Autodesk Fusion 360 part; units mm, degrees
(part 14 of 28)
  line L615 (34.2647, -13.2503) -> (34.3599, -13.4408)
  line L616 (34.3599, -13.4408) -> (34.3599, -13.6313)
  line L617 (34.3599, -13.6313) -> (34.2647, -13.917)
  line L618 (34.2647, -13.917) -> (33.1218, -15.0598)
  line L619 (33.1218, -15.0598) -> (34.3599, -15.0598)
  line L620 (36.7409, -15.0598) -> (36.7409, -13.0598)
  line L621 (37.598, -15.0598) -> (37.598, -14.0122)
  line L622 (37.598, -14.0122) -> (37.5028, -13.8217)
  line L623 (37.5028, -13.8217) -> (37.3123, -13.7265)
  line L624 (37.3123, -13.7265) -> (37.0266, -13.7265)
  line L625 (37.0266, -13.7265) -> (36.8361, -13.8217)
  line L626 (36.8361, -13.8217) -> (36.7409, -13.917)
  line L627 (38.8361, -15.0598) -> (38.6456, -14.9646)
  line L628 (38.6456, -14.9646) -> (38.5504, -14.8694)
  line L629 (38.5504, -14.8694) -> (38.4552, -14.6789)
  line L630 (38.4552, -14.6789) -> (38.4552, -14.1075)
  line L631 (38.4552, -14.1075) -> (38.5504, -13.917)
  line L632 (38.5504, -13.917) -> (38.6456, -13.8217)
  line L633 (38.6456, -13.8217) -> (38.8361, -13.7265)
  line L634 (38.8361, -13.7265) -> (39.1218, -13.7265)
  line L635 (39.1218, -13.7265) -> (39.3123, -13.8217)
  line L636 (39.3123, -13.8217) -> (39.4075, -13.917)
  line L637 (39.4075, -13.917) -> (39.5028, -14.1075)
  line L638 (39.5028, -14.1075) -> (39.5028, -14.6789)
  line L639 (39.5028, -14.6789) -> (39.4075, -14.8694)
  line L640 (39.4075, -14.8694) -> (39.3123, -14.9646)
  line L641 (39.3123, -14.9646) -> (39.1218, -15.0598)
  line L642 (39.1218, -15.0598) -> (38.8361, -15.0598)
  line L643 (40.6456, -15.0598) -> (40.4552, -14.9646)
  line L644 (40.4552, -14.9646) -> (40.3599, -14.7741)
  line L645 (40.3599, -14.7741) -> (40.3599, -13.0598)
  line L646 (42.1694, -14.9646) -> (41.979, -15.0598)
  line L647 (41.979, -15.0598) -> (41.598, -15.0598)
  line L648 (41.598, -15.0598) -> (41.4075, -14.9646)
  line L649 (41.4075, -14.9646) -> (41.3123, -14.7741)
  line L650 (41.3123, -14.7741) -> (41.3123, -14.0122)
  line L651 (41.3123, -14.0122) -> (41.4075, -13.8217)
  line L652 (41.4075, -13.8217) -> (41.598, -13.7265)
  line L653 (41.598, -13.7265) -> (41.979, -13.7265)
  line L654 (41.979, -13.7265) -> (42.1694, -13.8217)
  line L655 (42.1694, -13.8217) -> (42.2647, -14.0122)
  line L656 (42.2647, -14.0122) -> (42.2647, -14.2027)
  line L657 (42.2647, -14.2027) -> (41.3123, -14.3932)
  line L658 (43.0266, -14.9646) -> (43.2171, -15.0598)
  line L659 (43.2171, -15.0598) -> (43.598, -15.0598)
  line L660 (43.598, -15.0598) -> (43.7885, -14.9646)
  line L661 (43.7885, -14.9646) -> (43.8837, -14.7741)
  line L662 (43.8837, -14.7741) -> (43.8837, -14.6789)
  line L663 (43.8837, -14.6789) -> (43.7885, -14.4884)
  line L664 (43.7885, -14.4884) -> (43.598, -14.3932)
  line L665 (43.598, -14.3932) -> (43.3123, -14.3932)
  line L666 (43.3123, -14.3932) -> (43.1218, -14.2979)
  line L667 (43.1218, -14.2979) -> (43.0266, -14.1075)
  line L668 (43.0266, -14.1075) -> (43.0266, -14.0122)
  line L669 (43.0266, -14.0122) -> (43.1218, -13.8217)
  line L670 (43.1218, -13.8217) -> (43.3123, -13.7265)
  line L671 (43.3123, -13.7265) -> (43.598, -13.7265)
  line L672 (43.598, -13.7265) -> (43.7885, -13.8217)
  line L673 (44.5504, -15.8217) -> (44.6456, -15.7265)
  line L674 (44.6456, -15.7265) -> (44.8361, -15.4408)
  line L675 (44.8361, -15.4408) -> (44.9313, -15.2503)
  line L676 (44.9313, -15.2503) -> (45.0266, -14.9646)
  line L677 (45.0266, -14.9646) -> (45.1218, -14.4884)
  line L678 (45.1218, -14.4884) -> (45.1218, -14.1075)
  line L679 (45.1218, -14.1075) -> (45.0266, -13.6313)
  line L680 (45.0266, -13.6313) -> (44.9313, -13.3456)
  line L681 (44.9313, -13.3456) -> (44.8361, -13.1551)
  line L682 (44.8361, -13.1551) -> (44.6456, -12.8694)
  line L683 (44.6456, -12.8694) -> (44.5504, -12.7741)
  line L684 (-5.555, -16.335) -> (-5.555, -17.235)
  line L685 (-6.005, -16.785) -> (-5.105, -16.785)
  line L686 (-2.1163, -15.6998) -> (-1.9258, -15.6998)
  line L687 (-1.9258, -15.6998) -> (-1.7353, -15.7951)
  line L688 (-1.7353, -15.7951) -> (-1.6401, -15.8903)
  line L689 (-1.6401, -15.8903) -> (-1.5449, -16.0808)
  line L690 (-1.5449, -16.0808) -> (-1.4496, -16.4617)
  line L691 (-1.4496, -16.4617) -> (-1.4496, -16.9379)
  line L692 (-1.4496, -16.9379) -> (-1.5449, -17.3189)
  line L693 (-1.5449, -17.3189) -> (-1.6401, -17.5094)
  line L694 (-1.6401, -17.5094) -> (-1.7353, -17.6046)
  line L695 (-1.7353, -17.6046) -> (-1.9258, -17.6998)
  line L696 (-1.9258, -17.6998) -> (-2.1163, -17.6998)
  line L697 (-2.1163, -17.6998) -> (-2.3068, -17.6046)
  line L698 (-2.3068, -17.6046) -> (-2.402, -17.5094)
  line L699 (-2.402, -17.5094) -> (-2.4972, -17.3189)
  line L700 (-2.4972, -17.3189) -> (-2.5925, -16.9379)
  line L701 (-2.5925, -16.9379) -> (-2.5925, -16.4617)
  line L702 (-2.5925, -16.4617) -> (-2.4972, -16.0808)
  line L703 (-2.4972, -16.0808) -> (-2.402, -15.8903)
  line L704 (-2.402, -15.8903) -> (-2.3068, -15.7951)
  line L705 (-2.3068, -15.7951) -> (-2.1163, -15.6998)
  line L706 (-0.5925, -17.5094) -> (-0.4972, -17.6046)
  line L707 (-0.4972, -17.6046) -> (-0.5925, -17.6998)
  line L708 (-0.5925, -17.6998) -> (-0.6877, -17.6046)
  line L709 (-0.6877, -17.6046) -> (-0.5925, -17.5094)
  line L710 (-0.5925, -17.5094) -> (-0.5925, -17.6998)
  line L711 (0.4551, -17.6998) -> (0.8361, -17.6998)
  line L712 (0.8361, -17.6998) -> (1.0266, -17.6046)
  line L713 (1.0266, -17.6046) -> (1.1218, -17.5094)
  line L714 (1.1218, -17.5094) -> (1.3123, -17.2236)
  line L715 (1.3123, -17.2236) -> (1.4075, -16.8427)
  line L716 (1.4075, -16.8427) -> (1.4075, -16.0808)
  line L717 (1.4075, -16.0808) -> (1.3123, -15.8903)
  line L718 (1.3123, -15.8903) -> (1.2171, -15.7951)
  line L719 (1.2171, -15.7951) -> (1.0266, -15.6998)
  line L720 (1.0266, -15.6998) -> (0.6456, -15.6998)
  line L721 (0.6456, -15.6998) -> (0.4551, -15.7951)
  line L722 (0.4551, -15.7951) -> (0.3599, -15.8903)
  line L723 (0.3599, -15.8903) -> (0.2647, -16.0808)
  line L724 (0.2647, -16.0808) -> (0.2647, -16.557)
  line L725 (0.2647, -16.557) -> (0.3599, -16.7475)
  line L726 (0.3599, -16.7475) -> (0.4551, -16.8427)
  line L727 (0.4551, -16.8427) -> (0.6456, -16.9379)
  line L728 (0.6456, -16.9379) -> (1.0266, -16.9379)
  line L729 (1.0266, -16.9379) -> (1.2171, -16.8427)
  line L730 (1.2171, -16.8427) -> (1.3123, -16.7475)
  line L731 (1.3123, -16.7475) -> (1.4075, -16.557)
  line L732 (2.6456, -15.6998) -> (2.8361, -15.6998)
  line L733 (2.8361, -15.6998) -> (3.0266, -15.7951)
  line L734 (3.0266, -15.7951) -> (3.1218, -15.8903)
  line L735 (3.1218, -15.8903) -> (3.2171, -16.0808)
  line L736 (3.2171, -16.0808) -> (3.3123, -16.4617)
  line L737 (3.3123, -16.4617) -> (3.3123, -16.9379)
  line L738 (3.3123, -16.9379) -> (3.2171, -17.3189)
  line L739 (3.2171, -17.3189) -> (3.1218, -17.5094)
  line L740 (3.1218, -17.5094) -> (3.0266, -17.6046)
  line L741 (3.0266, -17.6046) -> (2.8361, -17.6998)
  line L742 (2.8361, -17.6998) -> (2.6456, -17.6998)
  line L743 (2.6456, -17.6998) -> (2.4551, -17.6046)
  line L744 (2.4551, -17.6046) -> (2.3599, -17.5094)
  line L745 (2.3599, -17.5094) -> (2.2647, -17.3189)
  line L746 (2.2647, -17.3189) -> (2.1694, -16.9379)
  line L747 (2.1694, -16.9379) -> (2.1694, -16.4617)
  line L748 (2.1694, -16.4617) -> (2.2647, -16.0808)
  line L749 (2.2647, -16.0808) -> (2.3599, -15.8903)
  line L750 (2.3599, -15.8903) -> (2.4551, -15.7951)
  line L751 (2.4551, -15.7951) -> (2.6456, -15.6998)
  line L752 (4.5504, -15.6998) -> (4.7409, -15.6998)
  line L753 (4.7409, -15.6998) -> (4.9313, -15.7951)
  line L754 (4.9313, -15.7951) -> (5.0266, -15.8903)
  line L755 (5.0266, -15.8903) -> (5.1218, -16.0808)
  line L756 (5.1218, -16.0808) -> (5.2171, -16.4617)
  line L757 (5.2171, -16.4617) -> (5.2171, -16.9379)
  line L758 (5.2171, -16.9379) -> (5.1218, -17.3189)
  line L759 (5.1218, -17.3189) -> (5.0266, -17.5094)
  line L760 (5.0266, -17.5094) -> (4.9313, -17.6046)
  line L761 (4.9313, -17.6046) -> (4.7409, -17.6998)
  line L762 (4.7409, -17.6998) -> (4.5504, -17.6998)
  line L763 (4.5504, -17.6998) -> (4.3599, -17.6046)
  line L764 (4.3599, -17.6046) -> (4.2647, -17.5094)
  line L765 (4.2647, -17.5094) -> (4.1694, -17.3189)
  line L766 (4.1694, -17.3189) -> (4.0742, -16.9379)
  line L767 (4.0742, -16.9379) -> (4.0742, -16.4617)
  line L768 (4.0742, -16.4617) -> (4.1694, -16.0808)
  line L769 (4.1694, -16.0808) -> (4.2647, -15.8903)
  line L770 (4.2647, -15.8903) -> (4.3599, -15.7951)
  line L771 (4.3599, -15.7951) -> (4.5504, -15.6998)
  line L772 (6.0742, -17.6998) -> (6.0742, -16.3665)
  line L773 (6.0742, -16.557) -> (6.1694, -16.4617)
  line L774 (6.1694, -16.4617) -> (6.3599, -16.3665)
  line L775 (6.3599, -16.3665) -> (6.6456, -16.3665)
  line L776 (6.6456, -16.3665) -> (6.8361, -16.4617)
  line L777 (6.8361, -16.4617) -> (6.9313, -16.6522)
  line L778 (6.9313, -16.6522) -> (6.9313, -17.6998)
  line L779 (6.9313, -16.6522) -> (7.0266, -16.4617)
  line L780 (7.0266, -16.4617) -> (7.2171, -16.3665)
  line L781 (7.2171, -16.3665) -> (7.5028, -16.3665)
  line L782 (7.5028, -16.3665) -> (7.6932, -16.4617)
  line L783 (7.6932, -16.4617) -> (7.7885, -16.6522)
  line L784 (7.7885, -16.6522) -> (7.7885, -17.6998)
  line L785 (8.7409, -17.6998) -> (8.7409, -16.3665)
  line L786 (8.7409, -16.557) -> (8.8361, -16.4617)
  line L787 (8.8361, -16.4617) -> (9.0266, -16.3665)
  line L788 (9.0266, -16.3665) -> (9.3123, -16.3665)
  line L789 (9.3123, -16.3665) -> (9.5028, -16.4617)
  line L790 (9.5028, -16.4617) -> (9.598, -16.6522)
  line L791 (9.598, -16.6522) -> (9.598, -17.6998)
  line L792 (9.598, -16.6522) -> (9.6932, -16.4617)
  line L793 (9.6932, -16.4617) -> (9.8837, -16.3665)
  line L794 (9.8837, -16.3665) -> (10.1694, -16.3665)
  line L795 (10.1694, -16.3665) -> (10.3599, -16.4617)
  line L796 (10.3599, -16.4617) -> (10.4552, -16.6522)
  line L797 (10.4552, -16.6522) -> (10.4552, -17.6998)
  line L798 (14.3599, -15.6046) -> (12.6456, -18.176)
  line L799 (16.9313, -15.6998) -> (17.1218, -15.6998)
  line L800 (17.1218, -15.6998) -> (17.3123, -15.7951)
  line L801 (17.3123, -15.7951) -> (17.4075, -15.8903)
  line L802 (17.4075, -15.8903) -> (17.5028, -16.0808)
  line L803 (17.5028, -16.0808) -> (17.598, -16.4617)
  line L804 (17.598, -16.4617) -> (17.598, -16.9379)
  line L805 (17.598, -16.9379) -> (17.5028, -17.3189)
  line L806 (17.5028, -17.3189) -> (17.4075, -17.5094)
  line L807 (17.4075, -17.5094) -> (17.3123, -17.6046)
  line L808 (17.3123, -17.6046) -> (17.1218, -17.6998)
  line L809 (17.1218, -17.6998) -> (16.9313, -17.6998)
  line L810 (16.9313, -17.6998) -> (16.7409, -17.6046)
  line L811 (16.7409, -17.6046) -> (16.6456, -17.5094)
  line L812 (16.6456, -17.5094) -> (16.5504, -17.3189)
  line L813 (16.5504, -17.3189) -> (16.4552, -16.9379)
  line L814 (16.4552, -16.9379) -> (16.4552, -16.4617)
  line L815 (16.4552, -16.4617) -> (16.5504, -16.0808)
  line L816 (16.5504, -16.0808) -> (16.6456, -15.8903)
  line L817 (16.6456, -15.8903) -> (16.7409, -15.7951)
  line L818 (16.7409, -15.7951) -> (16.9313, -15.6998)
  line L819 (18.4552, -17.5094) -> (18.5504, -17.6046)
  line L820 (18.5504, -17.6046) -> (18.4552, -17.6998)
  line L821 (18.4552, -17.6998) -> (18.3599, -17.6046)
  line L822 (18.3599, -17.6046) -> (18.4552, -17.5094)
  line L823 (18.4552, -17.5094) -> (18.4552, -17.6998)
  line L824 (19.7885, -15.6998) -> (19.979, -15.6998)
  line L825 (19.979, -15.6998) -> (20.1694, -15.7951)
  line L826 (20.1694, -15.7951) -> (20.2647, -15.8903)
  line L827 (20.2647, -15.8903) -> (20.3599, -16.0808)
  line L828 (20.3599, -16.0808) -> (20.4552, -16.4617)
  line L829 (20.4552, -16.4617) -> (20.4552, -16.9379)
  line L830 (20.4552, -16.9379) -> (20.3599, -17.3189)
  line L831 (20.3599, -17.3189) -> (20.2647, -17.5094)
  line L832 (20.2647, -17.5094) -> (20.1694, -17.6046)
  line L833 (20.1694, -17.6046) -> (19.979, -17.6998)
  line L834 (19.979, -17.6998) -> (19.7885, -17.6998)
  line L835 (19.7885, -17.6998) -> (19.598, -17.6046)
  line L836 (19.598, -17.6046) -> (19.5028, -17.5094)
  line L837 (19.5028, -17.5094) -> (19.4075, -17.3189)
  line L838 (19.4075, -17.3189) -> (19.3123, -16.9379)
  line L839 (19.3123, -16.9379) -> (19.3123, -16.4617)
  line L840 (19.3123, -16.4617) -> (19.4075, -16.0808)
  line L841 (19.4075, -16.0808) -> (19.5028, -15.8903)
  line L842 (19.5028, -15.8903) -> (19.598, -15.7951)
  line L843 (19.598, -15.7951) -> (19.7885, -15.6998)
  line L844 (21.1218, -15.6998) -> (22.3599, -15.6998)
  line L845 (22.3599, -15.6998) -> (21.6932, -16.4617)
  line L846 (21.6932, -16.4617) -> (21.979, -16.4617)
  line L847 (21.979, -16.4617) -> (22.1694, -16.557)
  line L848 (22.1694, -16.557) -> (22.2647, -16.6522)
  line L849 (22.2647, -16.6522) -> (22.3599, -16.8427)
  line L850 (22.3599, -16.8427) -> (22.3599, -17.3189)
  line L851 (22.3599, -17.3189) -> (22.2647, -17.5094)
  line L852 (22.2647, -17.5094) -> (22.1694, -17.6046)
  line L853 (22.1694, -17.6046) -> (21.979, -17.6998)
  line L854 (21.979, -17.6998) -> (21.4075, -17.6998)
  line L855 (21.4075, -17.6998) -> (21.2171, -17.6046)
  line L856 (21.2171, -17.6046) -> (21.1218, -17.5094)
  line L857 (24.1694, -15.6998) -> (23.2171, -15.6998)
  line L858 (23.2171, -15.6998) -> (23.1218, -16.6522)
  line L859 (23.1218, -16.6522) -> (23.2171, -16.557)
  line L860 (23.2171, -16.557) -> (23.4075, -16.4617)
  line L861 (23.4075, -16.4617) -> (23.8837, -16.4617)
  line L862 (23.8837, -16.4617) -> (24.0742, -16.557)
  line L863 (24.0742, -16.557) -> (24.1694, -16.6522)
  line L864 (24.1694, -16.6522) -> (24.2647, -16.8427)
  line L865 (24.2647, -16.8427) -> (24.2647, -17.3189)
  line L866 (24.2647, -17.3189) -> (24.1694, -17.5094)
  line L867 (24.1694, -17.5094) -> (24.0742, -17.6046)
  line L868 (24.0742, -17.6046) -> (23.8837, -17.6998)
  line L869 (23.8837, -17.6998) -> (23.4075, -17.6998)
  line L870 (23.4075, -17.6998) -> (23.2171, -17.6046)
  line L871 (23.2171, -17.6046) -> (23.1218, -17.5094)
  line L872 (25.979, -16.3665) -> (25.979, -17.6998)
  line L873 (25.5028, -15.6046) -> (25.0266, -17.0332)
  line L874 (25.0266, -17.0332) -> (26.2647, -17.0332)
  line L875 (26.9313, -15.6998) -> (26.9313, -16.0808)
  line L876 (27.6932, -15.6998) -> (27.6932, -16.0808)
  line L877 (30.6456, -18.4617) -> (30.5504, -18.3665)
  line L878 (30.5504, -18.3665) -> (30.3599, -18.0808)
  line L879 (30.3599, -18.0808) -> (30.2647, -17.8903)
  line L880 (30.2647, -17.8903) -> (30.1694, -17.6046)
  line L881 (30.1694, -17.6046) -> (30.0742, -17.1284)
  line L882 (30.0742, -17.1284) -> (30.0742, -16.7475)
  line L883 (30.0742, -16.7475) -> (30.1694, -16.2713)
  line L884 (30.1694, -16.2713) -> (30.2647, -15.9856)
  line L885 (30.2647, -15.9856) -> (30.3599, -15.7951)
  line L886 (30.3599, -15.7951) -> (30.5504, -15.5094)
  line L887 (30.5504, -15.5094) -> (30.6456, -15.4141)
  line L888 (32.4552, -17.6998) -> (31.3123, -17.6998)
  line L889 (31.8837, -17.6998) -> (31.8837, -15.6998)
  line L890 (31.8837, -15.6998) -> (31.6932, -15.9856)
  line L891 (31.6932, -15.9856) -> (31.5028, -16.176)
  line L892 (31.5028, -16.176) -> (31.3123, -16.2713)
  line L893 (33.2171, -15.8903) -> (33.3123, -15.7951)
  line L894 (33.3123, -15.7951) -> (33.5028, -15.6998)
  line L895 (33.5028, -15.6998) -> (33.979, -15.6998)
  line L896 (33.979, -15.6998) -> (34.1694, -15.7951)
  line L897 (34.1694, -15.7951) -> (34.2647, -15.8903)
  line L898 (34.2647, -15.8903) -> (34.3599, -16.0808)
  line L899 (34.3599, -16.0808) -> (34.3599, -16.2713)
  line L900 (34.3599, -16.2713) -> (34.2647, -16.557)
  line L901 (34.2647, -16.557) -> (33.1218, -17.6998)
  line L902 (33.1218, -17.6998) -> (34.3599, -17.6998)
  line L903 (36.7409, -17.6998) -> (36.7409, -15.6998)
  line L904 (37.598, -17.6998) -> (37.598, -16.6522)
  line L905 (37.598, -16.6522) -> (37.5028, -16.4617)
  line L906 (37.5028, -16.4617) -> (37.3123, -16.3665)
  line L907 (37.3123, -16.3665) -> (37.0266, -16.3665)
  line L908 (37.0266, -16.3665) -> (36.8361, -16.4617)
  line L909 (36.8361, -16.4617) -> (36.7409, -16.557)
  line L910 (38.8361, -17.6998) -> (38.6456, -17.6046)
  line L911 (38.6456, -17.6046) -> (38.5504, -17.5094)
  line L912 (38.5504, -17.5094) -> (38.4552, -17.3189)
  line L913 (38.4552, -17.3189) -> (38.4552, -16.7475)
  line L914 (38.4552, -16.7475) -> (38.5504, -16.557)
  line L915 (38.5504, -16.557) -> (38.6456, -16.4617)
  line L916 (38.6456, -16.4617) -> (38.8361, -16.3665)
  line L917 (38.8361, -16.3665) -> (39.1218, -16.3665)
  line L918 (39.1218, -16.3665) -> (39.3123, -16.4617)
  line L919 (39.3123, -16.4617) -> (39.4075, -16.557)
  line L920 (39.4075, -16.557) -> (39.5028, -16.7475)
  line L921 (39.5028, -16.7475) -> (39.5028, -17.3189)
  line L922 (39.5028, -17.3189) -> (39.4075, -17.5094)
  line L923 (39.4075, -17.5094) -> (39.3123, -17.6046)
  line L924 (39.3123, -17.6046) -> (39.1218, -17.6998)
  line L925 (39.1218, -17.6998) -> (38.8361, -17.6998)
  line L926 (40.6456, -17.6998) -> (40.4552, -17.6046)
  line L927 (40.4552, -17.6046) -> (40.3599, -17.4141)
  line L928 (40.3599, -17.4141) -> (40.3599, -15.6998)
  line L929 (42.1694, -17.6046) -> (41.979, -17.6998)
  line L930 (41.979, -17.6998) -> (41.598, -17.6998)
  line L931 (41.598, -17.6998) -> (41.4075, -17.6046)
  line L932 (41.4075, -17.6046) -> (41.3123, -17.4141)
  line L933 (41.3123, -17.4141) -> (41.3123, -16.6522)
  line L934 (41.3123, -16.6522) -> (41.4075, -16.4617)
  line L935 (41.4075, -16.4617) -> (41.598, -16.3665)
  line L936 (41.598, -16.3665) -> (41.979, -16.3665)
  line L937 (41.979, -16.3665) -> (42.1694, -16.4617)
  line L938 (42.1694, -16.4617) -> (42.2647, -16.6522)
  line L939 (42.2647, -16.6522) -> (42.2647, -16.8427)
  line L940 (42.2647, -16.8427) -> (41.3123, -17.0332)
  line L941 (43.0266, -17.6046) -> (43.2171, -17.6998)
  line L942 (43.2171, -17.6998) -> (43.598, -17.6998)
  line L943 (43.598, -17.6998) -> (43.7885, -17.6046)
  line L944 (43.7885, -17.6046) -> (43.8837, -17.4141)
  line L945 (43.8837, -17.4141) -> (43.8837, -17.3189)
  line L946 (43.8837, -17.3189) -> (43.7885, -17.1284)
  line L947 (43.7885, -17.1284) -> (43.598, -17.0332)
  line L948 (43.598, -17.0332) -> (43.3123, -17.0332)
  line L949 (43.3123, -17.0332) -> (43.1218, -16.9379)
  line L950 (43.1218, -16.9379) -> (43.0266, -16.7475)
  line L951 (43.0266, -16.7475) -> (43.0266, -16.6522)
  line L952 (43.0266, -16.6522) -> (43.1218, -16.4617)
  line L953 (43.1218, -16.4617) -> (43.3123, -16.3665)
  line L954 (43.3123, -16.3665) -> (43.598, -16.3665)
  line L955 (43.598, -16.3665) -> (43.7885, -16.4617)
  line L956 (44.5504, -18.4617) -> (44.6456, -18.3665)
  line L957 (44.6456, -18.3665) -> (44.8361, -18.0808)
  line L958 (44.8361, -18.0808) -> (44.9313, -17.8903)
  line L959 (44.9313, -17.8903) -> (45.0266, -17.6046)
  line L960 (45.0266, -17.6046) -> (45.1218, -17.1284)
  line L961 (45.1218, -17.1284) -> (45.1218, -16.7475)
  line L962 (45.1218, -16.7475) -> (45.0266, -16.2713)
  line L963 (45.0266, -16.2713) -> (44.9313, -15.9856)
  line L964 (44.9313, -15.9856) -> (44.8361, -15.7951)
  line L965 (44.8361, -15.7951) -> (44.6456, -15.5094)
  line L966 (44.6456, -15.5094) -> (44.5504, -15.4141)
  line L967 (-5.2514, -19.7786) -> (-5.2514, -19.0714)
  line L968 (-5.2514, -19.0714) -> (-5.9586, -19.0714)
  line L969 (-5.9586, -19.0714) -> (-5.9586, -19.7786)
  line L970 (-5.9586, -19.7786) -> (-5.2514, -19.7786)
  line L971 (-1.4496, -20.3398) -> (-2.5925, -20.3398)
  line L972 (-2.021, -20.3398) -> (-2.021, -18.3398)
  line L973 (-2.021, -18.3398) -> (-2.2115, -18.6256)
  line L974 (-2.2115, -18.6256) -> (-2.402, -18.816)
  line L975 (-2.402, -18.816) -> (-2.5925, -18.9113)
  line L976 (-0.5925, -20.1494) -> (-0.4972, -20.2446)
  line L977 (-0.4972, -20.2446) -> (-0.5925, -20.3398)
  line L978 (-0.5925, -20.3398) -> (-0.6877, -20.2446)
  line L979 (-0.6877, -20.2446) -> (-0.5925, -20.1494)
  line L980 (-0.5925, -20.1494) -> (-0.5925, -20.3398)
  line L981 (0.7409, -18.3398) -> (0.9313, -18.3398)
  line L982 (0.9313, -18.3398) -> (1.1218, -18.4351)
  line L983 (1.1218, -18.4351) -> (1.2171, -18.5303)
  line L984 (1.2171, -18.5303) -> (1.3123, -18.7208)
  line L985 (1.3123, -18.7208) -> (1.4075, -19.1017)
  line L986 (1.4075, -19.1017) -> (1.4075, -19.5779)
  line L987 (1.4075, -19.5779) -> (1.3123, -19.9589)
  line L988 (1.3123, -19.9589) -> (1.2171, -20.1494)
  line L989 (1.2171, -20.1494) -> (1.1218, -20.2446)
  line L990 (1.1218, -20.2446) -> (0.9313, -20.3398)
  line L991 (0.9313, -20.3398) -> (0.7409, -20.3398)
  line L992 (0.7409, -20.3398) -> (0.5504, -20.2446)
  line L993 (0.5504, -20.2446) -> (0.4551, -20.1494)
  line L994 (0.4551, -20.1494) -> (0.3599, -19.9589)
  line L995 (0.3599, -19.9589) -> (0.2647, -19.5779)
  line L996 (0.2647, -19.5779) -> (0.2647, -19.1017)
  line L997 (0.2647, -19.1017) -> (0.3599, -18.7208)
  line L998 (0.3599, -18.7208) -> (0.4551, -18.5303)
  line L999 (0.4551, -18.5303) -> (0.5504, -18.4351)
  line L1000 (0.5504, -18.4351) -> (0.7409, -18.3398)
  line L1001 (2.6456, -18.3398) -> (2.8361, -18.3398)
  line L1002 (2.8361, -18.3398) -> (3.0266, -18.4351)
  line L1003 (3.0266, -18.4351) -> (3.1218, -18.5303)
  line L1004 (3.1218, -18.5303) -> (3.2171, -18.7208)
  line L1005 (3.2171, -18.7208) -> (3.3123, -19.1017)
  line L1006 (3.3123, -19.1017) -> (3.3123, -19.5779)
  line L1007 (3.3123, -19.5779) -> (3.2171, -19.9589)
  line L1008 (3.2171, -19.9589) -> (3.1218, -20.1494)
  line L1009 (3.1218, -20.1494) -> (3.0266, -20.2446)
  line L1010 (3.0266, -20.2446) -> (2.8361, -20.3398)
  line L1011 (2.8361, -20.3398) -> (2.6456, -20.3398)
  line L1012 (2.6456, -20.3398) -> (2.4551, -20.2446)
  line L1013 (2.4551, -20.2446) -> (2.3599, -20.1494)
  line L1014 (2.3599, -20.1494) -> (2.2647, -19.9589)
  line L1015 (2.2647, -19.9589) -> (2.1694, -19.5779)
  line L1016 (2.1694, -19.5779) -> (2.1694, -19.1017)
  line L1017 (2.1694, -19.1017) -> (2.2647, -18.7208)
  line L1018 (2.2647, -18.7208) -> (2.3599, -18.5303)
  line L1019 (2.3599, -18.5303) -> (2.4551, -18.4351)
  line L1020 (2.4551, -18.4351) -> (2.6456, -18.3398)
  line L1021 (4.5504, -18.3398) -> (4.7409, -18.3398)
  line L1022 (4.7409, -18.3398) -> (4.9313, -18.4351)
  line L1023 (4.9313, -18.4351) -> (5.0266, -18.5303)
  line L1024 (5.0266, -18.5303) -> (5.1218, -18.7208)
  line L1025 (5.1218, -18.7208) -> (5.2171, -19.1017)
  line L1026 (5.2171, -19.1017) -> (5.2171, -19.5779)
  line L1027 (5.2171, -19.5779) -> (5.1218, -19.9589)
  line L1028 (5.1218, -19.9589) -> (5.0266, -20.1494)
  line L1029 (5.0266, -20.1494) -> (4.9313, -20.2446)
  line L1030 (4.9313, -20.2446) -> (4.7409, -20.3398)
  line L1031 (4.7409, -20.3398) -> (4.5504, -20.3398)
  line L1032 (4.5504, -20.3398) -> (4.3599, -20.2446)
  line L1033 (4.3599, -20.2446) -> (4.2647, -20.1494)
  line L1034 (4.2647, -20.1494) -> (4.1694, -19.9589)
  line L1035 (4.1694, -19.9589) -> (4.0742, -19.5779)
  line L1036 (4.0742, -19.5779) -> (4.0742, -19.1017)
  line L1037 (4.0742, -19.1017) -> (4.1694, -18.7208)
  line L1038 (4.1694, -18.7208) -> (4.2647, -18.5303)
  line L1039 (4.2647, -18.5303) -> (4.3599, -18.4351)
  line L1040 (4.3599, -18.4351) -> (4.5504, -18.3398)
  line L1041 (6.0742, -20.3398) -> (6.0742, -19.0065)
  line L1042 (6.0742, -19.197) -> (6.1694, -19.1017)
  line L1043 (6.1694, -19.1017) -> (6.3599, -19.0065)
  line L1044 (6.3599, -19.0065) -> (6.6456, -19.0065)
  line L1045 (6.6456, -19.0065) -> (6.8361, -19.1017)
  line L1046 (6.8361, -19.1017) -> (6.9313, -19.2922)
  line L1047 (6.9313, -19.2922) -> (6.9313, -20.3398)
  line L1048 (6.9313, -19.2922) -> (7.0266, -19.1017)
  line L1049 (7.0266, -19.1017) -> (7.2171, -19.0065)
  line L1050 (7.2171, -19.0065) -> (7.5028, -19.0065)
  line L1051 (7.5028, -19.0065) -> (7.6932, -19.1017)
  line L1052 (7.6932, -19.1017) -> (7.7885, -19.2922)
  line L1053 (7.7885, -19.2922) -> (7.7885, -20.3398)
  line L1054 (8.7409, -20.3398) -> (8.7409, -19.0065)
  line L1055 (8.7409, -19.197) -> (8.8361, -19.1017)
  line L1056 (8.8361, -19.1017) -> (9.0266, -19.0065)
  line L1057 (9.0266, -19.0065) -> (9.3123, -19.0065)
  line L1058 (9.3123, -19.0065) -> (9.5028, -19.1017)
  line L1059 (9.5028, -19.1017) -> (9.598, -19.2922)
  line L1060 (9.598, -19.2922) -> (9.598, -20.3398)
  line L1061 (9.598, -19.2922) -> (9.6932, -19.1017)
  line L1062 (9.6932, -19.1017) -> (9.8837, -19.0065)
  line L1063 (9.8837, -19.0065) -> (10.1694, -19.0065)
  line L1064 (10.1694, -19.0065) -> (10.3599, -19.1017)
  line L1065 (10.3599, -19.1017) -> (10.4552, -19.2922)
  line L1066 (10.4552, -19.2922) -> (10.4552, -20.3398)
  line L1067 (14.3599, -18.2446) -> (12.6456, -20.816)
  line L1068 (16.9313, -18.3398) -> (17.1218, -18.3398)
  line L1069 (17.1218, -18.3398) -> (17.3123, -18.4351)
  line L1070 (17.3123, -18.4351) -> (17.4075, -18.5303)
  line L1071 (17.4075, -18.5303) -> (17.5028, -18.7208)
  line L1072 (17.5028, -18.7208) -> (17.598, -19.1017)
  line L1073 (17.598, -19.1017) -> (17.598, -19.5779)
  line L1074 (17.598, -19.5779) -> (17.5028, -19.9589)
  line L1075 (17.5028, -19.9589) -> (17.4075, -20.1494)
  line L1076 (17.4075, -20.1494) -> (17.3123, -20.2446)
  line L1077 (17.3123, -20.2446) -> (17.1218, -20.3398)
  line L1078 (17.1218, -20.3398) -> (16.9313, -20.3398)
  line L1079 (16.9313, -20.3398) -> (16.7409, -20.2446)
  line L1080 (16.7409, -20.2446) -> (16.6456, -20.1494)
  line L1081 (16.6456, -20.1494) -> (16.5504, -19.9589)
  line L1082 (16.5504, -19.9589) -> (16.4552, -19.5779)
  line L1083 (16.4552, -19.5779) -> (16.4552, -19.1017)
  line L1084 (16.4552, -19.1017) -> (16.5504, -18.7208)
  line L1085 (16.5504, -18.7208) -> (16.6456, -18.5303)
  line L1086 (16.6456, -18.5303) -> (16.7409, -18.4351)
  line L1087 (16.7409, -18.4351) -> (16.9313, -18.3398)
  line L1088 (18.4552, -20.1494) -> (18.5504, -20.2446)
  line L1089 (18.5504, -20.2446) -> (18.4552, -20.3398)
  line L1090 (18.4552, -20.3398) -> (18.3599, -20.2446)
  line L1091 (18.3599, -20.2446) -> (18.4552, -20.1494)
  line L1092 (18.4552, -20.1494) -> (18.4552, -20.3398)
  line L1093 (19.7885, -18.3398) -> (19.979, -18.3398)
  line L1094 (19.979, -18.3398) -> (20.1694, -18.4351)
  line L1095 (20.1694, -18.4351) -> (20.2647, -18.5303)
  line L1096 (20.2647, -18.5303) -> (20.3599, -18.7208)
  line L1097 (20.3599, -18.7208) -> (20.4552, -19.1017)
  line L1098 (20.4552, -19.1017) -> (20.4552, -19.5779)
  line L1099 (20.4552, -19.5779) -> (20.3599, -19.9589)
  line L1100 (20.3599, -19.9589) -> (20.2647, -20.1494)
  line L1101 (20.2647, -20.1494) -> (20.1694, -20.2446)
  line L1102 (20.1694, -20.2446) -> (19.979, -20.3398)
  line L1103 (19.979, -20.3398) -> (19.7885, -20.3398)
  line L1104 (19.7885, -20.3398) -> (19.598, -20.2446)
  line L1105 (19.598, -20.2446) -> (19.5028, -20.1494)
  line L1106 (19.5028, -20.1494) -> (19.4075, -19.9589)
  line L1107 (19.4075, -19.9589) -> (19.3123, -19.5779)
  line L1108 (19.3123, -19.5779) -> (19.3123, -19.1017)
  line L1109 (19.3123, -19.1017) -> (19.4075, -18.7208)
  line L1110 (19.4075, -18.7208) -> (19.5028, -18.5303)
  line L1111 (19.5028, -18.5303) -> (19.598, -18.4351)
  line L1112 (19.598, -18.4351) -> (19.7885, -18.3398)
  line L1113 (21.1218, -18.3398) -> (22.3599, -18.3398)
  line L1114 (22.3599, -18.3398) -> (21.6932, -19.1017)
  line L1115 (21.6932, -19.1017) -> (21.979, -19.1017)
  line L1116 (21.979, -19.1017) -> (22.1694, -19.197)
  line L1117 (22.1694, -19.197) -> (22.2647, -19.2922)
  line L1118 (22.2647, -19.2922) -> (22.3599, -19.4827)
  line L1119 (22.3599, -19.4827) -> (22.3599, -19.9589)
  line L1120 (22.3599, -19.9589) -> (22.2647, -20.1494)
  line L1121 (22.2647, -20.1494) -> (22.1694, -20.2446)
  line L1122 (22.1694, -20.2446) -> (21.979, -20.3398)
  line L1123 (21.979, -20.3398) -> (21.4075, -20.3398)
  line L1124 (21.4075, -20.3398) -> (21.2171, -20.2446)
  line L1125 (21.2171, -20.2446) -> (21.1218, -20.1494)
  line L1126 (23.3123, -20.3398) -> (23.6932, -20.3398)
  line L1127 (23.6932, -20.3398) -> (23.8837, -20.2446)
  line L1128 (23.8837, -20.2446) -> (23.979, -20.1494)
  line L1129 (23.979, -20.1494) -> (24.1694, -19.8636)
  line L1130 (24.1694, -19.8636) -> (24.2647, -19.4827)
  line L1131 (24.2647, -19.4827) -> (24.2647, -18.7208)
  line L1132 (24.2647, -18.7208) -> (24.1694, -18.5303)
  line L1133 (24.1694, -18.5303) -> (24.0742, -18.4351)
  line L1134 (24.0742, -18.4351) -> (23.8837, -18.3398)
  line L1135 (23.8837, -18.3398) -> (23.5028, -18.3398)
  line L1136 (23.5028, -18.3398) -> (23.3123, -18.4351)
  line L1137 (23.3123, -18.4351) -> (23.2171, -18.5303)
  line L1138 (23.2171, -18.5303) -> (23.1218, -18.7208)
  line L1139 (23.1218, -18.7208) -> (23.1218, -19.197)
  line L1140 (23.1218, -19.197) -> (23.2171, -19.3875)
  line L1141 (23.2171, -19.3875) -> (23.3123, -19.4827)
  line L1142 (23.3123, -19.4827) -> (23.5028, -19.5779)
  line L1143 (23.5028, -19.5779) -> (23.8837, -19.5779)
  line L1144 (23.8837, -19.5779) -> (24.0742, -19.4827)
  line L1145 (24.0742, -19.4827) -> (24.1694, -19.3875)
  line L1146 (24.1694, -19.3875) -> (24.2647, -19.197)
  line L1147 (25.979, -19.0065) -> (25.979, -20.3398)
  line L1148 (25.5028, -18.2446) -> (25.0266, -19.6732)
  line L1149 (25.0266, -19.6732) -> (26.2647, -19.6732)
  line L1150 (26.9313, -18.3398) -> (26.9313, -18.7208)
  line L1151 (27.6932, -18.3398) -> (27.6932, -18.7208)
  line L1152 (30.6456, -21.1017) -> (30.5504, -21.0065)
  line L1153 (30.5504, -21.0065) -> (30.3599, -20.7208)
  line L1154 (30.3599, -20.7208) -> (30.2647, -20.5303)
  line L1155 (30.2647, -20.5303) -> (30.1694, -20.2446)
  line L1156 (30.1694, -20.2446) -> (30.0742, -19.7684)
  line L1157 (30.0742, -19.7684) -> (30.0742, -19.3875)
  line L1158 (30.0742, -19.3875) -> (30.1694, -18.9113)
  line L1159 (30.1694, -18.9113) -> (30.2647, -18.6256)
  line L1160 (30.2647, -18.6256) -> (30.3599, -18.4351)
  line L1161 (30.3599, -18.4351) -> (30.5504, -18.1494)
  line L1162 (30.5504, -18.1494) -> (30.6456, -18.0541)
  line L1163 (32.4552, -20.3398) -> (31.3123, -20.3398)
  line L1164 (31.8837, -20.3398) -> (31.8837, -18.3398)
  line L1165 (31.8837, -18.3398) -> (31.6932, -18.6256)
  line L1166 (31.6932, -18.6256) -> (31.5028, -18.816)
  line L1167 (31.5028, -18.816) -> (31.3123, -18.9113)
  line L1168 (33.2171, -18.5303) -> (33.3123, -18.4351)
  line L1169 (33.3123, -18.4351) -> (33.5028, -18.3398)
  line L1170 (33.5028, -18.3398) -> (33.979, -18.3398)
  line L1171 (33.979, -18.3398) -> (34.1694, -18.4351)
  line L1172 (34.1694, -18.4351) -> (34.2647, -18.5303)
  line L1173 (34.2647, -18.5303) -> (34.3599, -18.7208)
  line L1174 (34.3599, -18.7208) -> (34.3599, -18.9113)
  line L1175 (34.3599, -18.9113) -> (34.2647, -19.197)
  line L1176 (34.2647, -19.197) -> (33.1218, -20.3398)
  line L1177 (33.1218, -20.3398) -> (34.3599, -20.3398)
  line L1178 (36.7409, -20.3398) -> (36.7409, -18.3398)
  line L1179 (37.598, -20.3398) -> (37.598, -19.2922)
  line L1180 (37.598, -19.2922) -> (37.5028, -19.1017)
  line L1181 (37.5028, -19.1017) -> (37.3123, -19.0065)
  line L1182 (37.3123, -19.0065) -> (37.0266, -19.0065)
  line L1183 (37.0266, -19.0065) -> (36.8361, -19.1017)
  line L1184 (36.8361, -19.1017) -> (36.7409, -19.197)
  line L1185 (38.8361, -20.3398) -> (38.6456, -20.2446)
  line L1186 (38.6456, -20.2446) -> (38.5504, -20.1494)
  line L1187 (38.5504, -20.1494) -> (38.4552, -19.9589)
  line L1188 (38.4552, -19.9589) -> (38.4552, -19.3875)
  line L1189 (38.4552, -19.3875) -> (38.5504, -19.197)
  line L1190 (38.5504, -19.197) -> (38.6456, -19.1017)
  line L1191 (38.6456, -19.1017) -> (38.8361, -19.0065)
  line L1192 (38.8361, -19.0065) -> (39.1218, -19.0065)
  line L1193 (39.1218, -19.0065) -> (39.3123, -19.1017)
  line L1194 (39.3123, -19.1017) -> (39.4075, -19.197)
  line L1195 (39.4075, -19.197) -> (39.5028, -19.3875)
  line L1196 (39.5028, -19.3875) -> (39.5028, -19.9589)
  line L1197 (39.5028, -19.9589) -> (39.4075, -20.1494)
  line L1198 (39.4075, -20.1494) -> (39.3123, -20.2446)
  line L1199 (39.3123, -20.2446) -> (39.1218, -20.3398)
  line L1200 (39.1218, -20.3398) -> (38.8361, -20.3398)
  line L1201 (40.6456, -20.3398) -> (40.4552, -20.2446)
  line L1202 (40.4552, -20.2446) -> (40.3599, -20.0541)
  line L1203 (40.3599, -20.0541) -> (40.3599, -18.3398)
  line L1204 (42.1694, -20.2446) -> (41.979, -20.3398)
  line L1205 (41.979, -20.3398) -> (41.598, -20.3398)
  line L1206 (41.598, -20.3398) -> (41.4075, -20.2446)
  line L1207 (41.4075, -20.2446) -> (41.3123, -20.0541)
  line L1208 (41.3123, -20.0541) -> (41.3123, -19.2922)
  line L1209 (41.3123, -19.2922) -> (41.4075, -19.1017)
  line L1210 (41.4075, -19.1017) -> (41.598, -19.0065)
  line L1211 (41.598, -19.0065) -> (41.979, -19.0065)
  line L1212 (41.979, -19.0065) -> (42.1694, -19.1017)
  line L1213 (42.1694, -19.1017) -> (42.2647, -19.2922)
  line L1214 (42.2647, -19.2922) -> (42.2647, -19.4827)
  line L1215 (42.2647, -19.4827) -> (41.3123, -19.6732)
  line L1216 (43.0266, -20.2446) -> (43.2171, -20.3398)
  line L1217 (43.2171, -20.3398) -> (43.598, -20.3398)
  line L1218 (43.598, -20.3398) -> (43.7885, -20.2446)
  line L1219 (43.7885, -20.2446) -> (43.8837, -20.0541)
  line L1220 (43.8837, -20.0541) -> (43.8837, -19.9589)
  line L1221 (43.8837, -19.9589) -> (43.7885, -19.7684)
  line L1222 (43.7885, -19.7684) -> (43.598, -19.6732)
  line L1223 (43.598, -19.6732) -> (43.3123, -19.6732)
  line L1224 (43.3123, -19.6732) -> (43.1218, -19.5779)
  line L1225 (43.1218, -19.5779) -> (43.0266, -19.3875)
  line L1226 (43.0266, -19.3875) -> (43.0266, -19.2922)
  line L1227 (43.0266, -19.2922) -> (43.1218, -19.1017)
  line L1228 (43.1218, -19.1017) -> (43.3123, -19.0065)
  line L1229 (43.3123, -19.0065) -> (43.598, -19.0065)
  line L1230 (43.598, -19.0065) -> (43.7885, -19.1017)
  line L1231 (44.5504, -21.1017) -> (44.6456, -21.0065)
  line L1232 (44.6456, -21.0065) -> (44.8361, -20.7208)
  line L1233 (44.8361, -20.7208) -> (44.9313, -20.5303)
  line L1234 (44.9313, -20.5303) -> (45.0266, -20.2446)
  line L1235 (45.0266, -20.2446) -> (45.1218, -19.7684)
  line L1236 (45.1218, -19.7684) -> (45.1218, -19.3875)
  line L1237 (45.1218, -19.3875) -> (45.0266, -18.9113)
  line L1238 (45.0266, -18.9113) -> (44.9313, -18.6256)
  line L1239 (44.9313, -18.6256) -> (44.8361, -18.4351)
  line L1240 (44.8361, -18.4351) -> (44.6456, -18.1494)
  line L1241 (44.6456, -18.1494) -> (44.5504, -18.0541)
  circle A1 centre (10.5488, 31.5592) radius 0.55
  circle A2 centre (10.5488, 29.0192) radius 0.55
  circle A3 centre (13.5258, 42.2988) radius 0.55
  circle A4 centre (16.0658, 42.2988) radius 0.55
  circle A5 centre (48.4508, 42.2988) radius 0.55
  circle A6 centre (50.9908, 42.2988) radius 0.55
  circle A7 centre (83.3758, 42.2988) radius 0.55
  circle A8 centre (85.9158, 42.2988) radius 0.55
  circle A9 centre (71.5088, 31.5592) radius 0.55
  circle A10 centre (71.5088, 29.0192) radius 0.55
  circle A11 centre (120.8408, 42.2988) radius 0.55
  circle A12 centre (118.3008, 42.2988) radius 0.55
  circle A13 centre (13.4065, 74.8985) radius 0.45
  circle A14 centre (16.1765, 74.8985) radius 0.45
  circle A15 centre (18.9065, 74.8985) radius 0.45
  circle A16 centre (23.9416, 74.8403) radius 0.45
  circle A17 centre (26.7116, 74.8403) radius 0.45
  circle A18 centre (29.4416, 74.8403) radius 0.45
  circle A19 centre (48.3315, 74.8985) radius 0.45
  circle A20 centre (51.1015, 74.8985) radius 0.45
  circle A21 centre (53.8315, 74.8985) radius 0.45
  circle A22 centre (58.8666, 74.8403) radius 0.45
  circle A23 centre (61.6366, 74.8403) radius 0.45
  circle A24 centre (64.3666, 74.8403) radius 0.45
  circle A25 centre (83.2565, 74.8985) radius 0.45
  circle A26 centre (86.0265, 74.8985) radius 0.45
  circle A27 centre (88.7565, 74.8985) radius 0.45
  circle A28 centre (93.7916, 74.8403) radius 0.45
  circle A29 centre (96.5616, 74.8403) radius 0.45
  circle A30 centre (99.2916, 74.8403) radius 0.45
  circle A31 centre (118.1815, 74.8985) radius 0.45
  circle A32 centre (120.9515, 74.8985) radius 0.45
  circle A33 centre (123.6815, 74.8985) radius 0.45
  circle A34 centre (128.7166, 74.8403) radius 0.45
  circle A35 centre (131.4866, 74.8403) radius 0.45
  circle A36 centre (134.2166, 74.8403) radius 0.45
  circle A37 centre (43.1485, 31.6785) radius 0.45
  circle A38 centre (43.1485, 28.9085) radius 0.45
  circle A39 centre (43.1485, 26.1785) radius 0.45
  circle A40 centre (43.0903, 21.1434) radius 0.45
  circle A41 centre (43.0903, 18.3734) radius 0.45
  circle A42 centre (43.0903, 15.6434) radius 0.45
  circle A43 centre (104.1085, 31.6785) radius 0.45
  circle A44 centre (104.1085, 28.9085) radius 0.45
  circle A45 centre (104.1085, 26.1785) radius 0.45
  circle A46 centre (104.0503, 21.1434) radius 0.45
  circle A47 centre (104.0503, 18.3734) radius 0.45
  circle A48 centre (104.0503, 15.6434) radius 0.45
  circle A49 centre (13.6297, 53.7531) radius 0.45
  circle A50 centre (16.1297, 53.7531) radius 0.45
  circle A51 centre (24.805, 53.34) radius 0.45
  circle A52 centre (27.305, 53.34) radius 0.45
  circle A53 centre (32.718, 61.0917) radius 0.45
  circle A54 centre (23.8079, 64.1718) radius 0.45
  circle A55 centre (16.1879, 64.1718) radius 0.45
  circle A56 centre (32.718, 68.7117) radius 0.45
  circle A57 centre (14.1442, 81.592) radius 0.45
  circle A58 centre (21.7642, 81.592) radius 0.45
  circle A59 centre (33.5677, 84.4375) radius 0.45
  circle A60 centre (33.5677, 92.0575) radius 0.45
  circle A61 centre (120.9629, 64.1718) radius 0.45
  circle A62 centre (128.5829, 64.1718) radius 0.45
  circle A63 centre (120.9047, 53.7531) radius 0.45
  circle A64 centre (118.4047, 53.7531) radius 0.45
  circle A65 centre (129.58, 53.34) radius 0.45
  circle A66 centre (132.08, 53.34) radius 0.45
  circle A67 centre (137.493, 61.0917) radius 0.45
  circle A68 centre (137.493, 68.7117) radius 0.45
  circle A69 centre (118.9192, 81.592) radius 0.45
  circle A70 centre (126.5392, 81.592) radius 0.45
  circle A71 centre (138.3427, 84.4375) radius 0.45
  circle A72 centre (138.3427, 92.0575) radius 0.45
  circle A73 centre (83.4797, 53.7531) radius 0.45
  circle A74 centre (85.9797, 53.7531) radius 0.45
  circle A75 centre (94.655, 53.34) radius 0.45
  circle A76 centre (97.155, 53.34) radius 0.45
  circle A77 centre (102.568, 61.0917) radius 0.45
  circle A78 centre (93.6579, 64.1718) radius 0.45
  circle A79 centre (86.0379, 64.1718) radius 0.45
  circle A80 centre (102.568, 68.7117) radius 0.45
  circle A81 centre (91.6142, 81.592) radius 0.45
  circle A82 centre (103.4177, 84.4375) radius 0.45
  circle A83 centre (103.4177, 92.0575) radius 0.45
  circle A84 centre (83.9942, 81.592) radius 0.45
  circle A85 centre (22.0031, 31.4553) radius 0.45
  circle A86 centre (22.0031, 28.9553) radius 0.45
  circle A87 centre (21.59, 17.78) radius 0.45
  circle A88 centre (21.59, 20.28) radius 0.45
  circle A89 centre (32.4218, 28.8971) radius 0.45
  circle A90 centre (32.4218, 21.2771) radius 0.45
  circle A91 centre (49.842, 23.3208) radius 0.45
  circle A92 centre (49.842, 30.9408) radius 0.45
  circle A93 centre (29.3417, 12.367) radius 0.45
  circle A94 centre (36.9617, 12.367) radius 0.45
  circle A95 centre (60.3075, 11.5173) radius 0.45
  circle A96 centre (52.6875, 11.5173) radius 0.45
  circle A97 centre (82.9631, 31.4553) radius 0.45
  circle A98 centre (82.9631, 28.9553) radius 0.45
  circle A99 centre (93.3818, 28.8971) radius 0.45
  circle A100 centre (82.55, 20.28) radius 0.45
  circle A101 centre (90.3017, 12.367) radius 0.45
  circle A102 centre (82.55, 17.78) radius 0.45
  circle A103 centre (97.9217, 12.367) radius 0.45
  circle A104 centre (113.6475, 11.5173) radius 0.45
  circle A105 centre (121.2675, 11.5173) radius 0.45
  circle A106 centre (110.802, 23.3208) radius 0.45
  circle A107 centre (110.802, 30.9408) radius 0.45
  circle A108 centre (93.3818, 21.2771) radius 0.45
  circle A109 centre (20.9874, 90.5733) radius 0.5
  circle A110 centre (23.5274, 90.5733) radius 0.5
  circle A111 centre (55.9124, 90.5733) radius 0.5
  circle A112 centre (58.4524, 90.5733) radius 0.5
  circle A113 centre (93.3774, 90.5733) radius 0.5
  circle A114 centre (90.8374, 90.5733) radius 0.5
  circle A115 centre (125.7624, 90.5733) radius 0.5
  circle A116 centre (128.3024, 90.5733) radius 0.5
  circle A117 centre (58.8233, 21.5576) radius 0.5
  circle A118 centre (58.8233, 24.0976) radius 0.5
  circle A119 centre (119.7833, 24.0976) radius 0.5
  circle A120 centre (119.7833, 21.5576) radius 0.5
  circle A121 centre (48.5547, 53.7531) radius 0.45
  circle A122 centre (51.0547, 53.7531) radius 0.45
  circle A123 centre (59.73, 53.34) radius 0.45
  circle A124 centre (62.23, 53.34) radius 0.45
  circle A125 centre (67.643, 61.0917) radius 0.45
  circle A126 centre (58.7329, 64.1718) radius 0.45
  circle A127 centre (51.1129, 64.1718) radius 0.45
  circle A128 centre (67.643, 68.7117) radius 0.45
  circle A129 centre (68.4927, 84.4375) radius 0.45
  circle A130 centre (56.6892, 81.592) radius 0.45
  circle A131 centre (49.0692, 81.592) radius 0.45
  circle A132 centre (68.4927, 92.0575) radius 0.45
  dimension "d12" = 1.1
  dimension "d13" = 1.1
  dimension "d14" = 1.1
  dimension "d15" = 1.1
  dimension "d16" = 1.1
  dimension "d17" = 1.1
  dimension "d18" = 1.1
  dimension "d19" = 1.1
  dimension "d20" = 1.1
  dimension "d21" = 1.1
  dimension "d22" = 1.1
  dimension "d23" = 1.1
  dimension "d32" = 0.9
  dimension "d33" = 0.9
  dimension "d34" = 0.9
  dimension "d35" = 0.9
  dimension "d36" = 0.9
  dimension "d37" = 0.9
  dimension "d38" = 0.9
  dimension "d39" = 0.9
  dimension "d40" = 0.9
  dimension "d41" = 0.9
  dimension "d42" = 0.9
  dimension "d43" = 0.9
  dimension "d44" = 0.9
  dimension "d45" = 0.9
  dimension "d46" = 0.9
  dimension "d47" = 0.9
  dimension "d48" = 0.9
  dimension "d49" = 0.9
  dimension "d50" = 0.9
  dimension "d51" = 0.9
  dimension "d52" = 0.9
  dimension "d53" = 0.9
  dimension "d54" = 0.9
  dimension "d55" = 0.9
  dimension "d56" = 0.9
  dimension "d57" = 0.9
  dimension "d58" = 0.9
  dimension "d59" = 0.9
  dimension "d60" = 0.9
  dimension "d61" = 0.9
  dimension "d62" = 0.9
  dimension "d63" = 0.9
  dimension "d64" = 0.9
  dimension "d65" = 0.9
  dimension "d66" = 0.9
  dimension "d67" = 0.9
  dimension "d68" = 0.9
  dimension "d69" = 0.9
  dimension "d70" = 0.9
  dimension "d71" = 0.9
  dimension "d72" = 0.9
  dimension "d73" = 0.9
  dimension "d74" = 0.9
  dimension "d75" = 0.9
  dimension "d76" = 0.9
  dimension "d77" = 0.9
  dimension "d78" = 0.9
  dimension "d79" = 0.9
  dimension "d80" = 0.9
  dimension "d81" = 0.9
  dimension "d82" = 0.9
  dimension "d83" = 0.9
  dimension "d84" = 0.9
  dimension "d85" = 0.9
  dimension "d86" = 0.9
  dimension "d87" = 0.9
  dimension "d88" = 0.9
  dimension "d89" = 0.9
  dimension "d90" = 0.9
  dimension "d91" = 0.9
  dimension "d92" = 0.9
  dimension "d93" = 0.9
  dimension "d94" = 0.9
  dimension "d95" = 0.9
  dimension "d96" = 0.9
  dimension "d97" = 0.9
  dimension "d98" = 0.9
  dimension "d99" = 0.9
  dimension "d100" = 0.9
  dimension "d101" = 0.9
  dimension "d102" = 0.9
  dimension "d103" = 0.9
  dimension "d104" = 0.9
  dimension "d105" = 0.9
  dimension "d106" = 0.9
  dimension "d107" = 0.9
  dimension "d108" = 0.9
  dimension "d109" = 0.9
  dimension "d110" = 0.9
  dimension "d111" = 0.9
  dimension "d112" = 0.9
  dimension "d113" = 0.9
  dimension "d114" = 0.9
  dimension "d115" = 0.9
  dimension "d116" = 0.9
  dimension "d117" = 0.9
  dimension "d118" = 0.9
  dimension "d119" = 0.9
  dimension "d120" = 0.9
  dimension "d121" = 0.9
  dimension "d122" = 0.9
  dimension "d123" = 0.9
  dimension "d124" = 0.9
  dimension "d125" = 0.9
  dimension "d126" = 0.9
  dimension "d127" = 0.9
  dimension "d128" = 1
  dimension "d129" = 1
  dimension "d131" = 1
  dimension "d132" = 1
  dimension "d133" = 1
  dimension "d134" = 1
  dimension "d135" = 1
  dimension "d136" = 1
  dimension "d137" = 1
  dimension "d138" = 1
  dimension "d139" = 1
  dimension "d140" = 1
  dimension "d141" = 0.9
  dimension "d142" = 0.9
  dimension "d143" = 0.9
  dimension "d144" = 0.9
  dimension "d145" = 0.9
  dimension "d146" = 0.9
  dimension "d147" = 0.9
  dimension "d148" = 0.9
  dimension "d149" = 0.9
  dimension "d150" = 0.9
  dimension "d151" = 0.9
  dimension "d152" = 0.9
  measures "d12" diameter of A1
  measures "d13" diameter of A2
  measures "d14" diameter of A3
  measures "d15" diameter of A4
  measures "d16" diameter of A5
  measures "d17" diameter of A6
  measures "d18" diameter of A7
  measures "d19" diameter of A8
  measures "d20" diameter of A9
  measures "d21" diameter of A10
  measures "d22" diameter of A11
  measures "d23" diameter of A12
  measures "d32" diameter of A13
  measures "d33" diameter of A14
  measures "d34" diameter of A15
  measures "d35" diameter of A16
  measures "d36" diameter of A17
  measures "d37" diameter of A18
  measures "d38" diameter of A19
  measures "d39" diameter of A20
  measures "d40" diameter of A21
  measures "d41" diameter of A22
  measures "d42" diameter of A23
  measures "d43" diameter of A24
  measures "d44" diameter of A25
  measures "d45" diameter of A26
  measures "d46" diameter of A27
  measures "d47" diameter of A28
  measures "d48" diameter of A29
  measures "d49" diameter of A30
  measures "d50" diameter of A31
  measures "d51" diameter of A32
  measures "d52" diameter of A33
  measures "d53" diameter of A34
  measures "d54" diameter of A35
  measures "d55" diameter of A36
  measures "d56" diameter of A37
  measures "d57" diameter of A38
  measures "d58" diameter of A39
  measures "d59" diameter of A40
  measures "d60" diameter of A41
  measures "d61" diameter of A42
  measures "d62" diameter of A43
  measures "d63" diameter of A44
  measures "d64" diameter of A45
  measures "d65" diameter of A46
  measures "d66" diameter of A47
  measures "d67" diameter of A48
  measures "d68" diameter of A49
  measures "d69" diameter of A50
  measures "d70" diameter of A51
  measures "d71" diameter of A52
  measures "d72" diameter of A53
  measures "d73" diameter of A54
  measures "d74" diameter of A55
  measures "d75" diameter of A56
  measures "d76" diameter of A57
  measures "d77" diameter of A58
  measures "d78" diameter of A59
  measures "d79" diameter of A60
  measures "d80" diameter of A64
  measures "d81" diameter of A63
  measures "d82" diameter of A65
  measures "d83" diameter of A66
  measures "d84" diameter of A67
  measures "d85" diameter of A62
  measures "d86" diameter of A61
  measures "d87" diameter of A68
  measures "d88" diameter of A69
  measures "d89" diameter of A70
  measures "d90" diameter of A71
  measures "d91" diameter of A72
  measures "d92" diameter of A73
  measures "d93" diameter of A74
  measures "d94" diameter of A75
  measures "d95" diameter of A76
  measures "d96" diameter of A77
  measures "d97" diameter of A78
  measures "d98" diameter of A79
  measures "d99" diameter of A80
  measures "d100" diameter of A84
  measures "d101" diameter of A81
  measures "d102" diameter of A82
  measures "d103" diameter of A83
  measures "d104" diameter of A85
  measures "d105" diameter of A86
  measures "d106" diameter of A88
  measures "d107" diameter of A87
  measures "d108" diameter of A89
  measures "d109" diameter of A90
  measures "d110" diameter of A92
  measures "d111" diameter of A91
  measures "d112" diameter of A93
  measures "d113" diameter of A94
  measures "d114" diameter of A96
  measures "d115" diameter of A95
  measures "d116" diameter of A97
  measures "d117" diameter of A98
  measures "d118" diameter of A100
  measures "d119" diameter of A102
  measures "d120" diameter of A99
  measures "d121" diameter of A108
  measures "d122" diameter of A107
  measures "d123" diameter of A106
  measures "d124" diameter of A101
  measures "d125" diameter of A103
  measures "d126" diameter of A104
  measures "d127" diameter of A105
  measures "d128" diameter of A109
  measures "d129" diameter of A110
  measures "d131" diameter of A111
  measures "d132" diameter of A112
  measures "d133" diameter of A114
  measures "d134" diameter of A113
  measures "d135" diameter of A115
  measures "d136" diameter of A116
  measures "d137" diameter of A117
  measures "d138" diameter of A118
  measures "d139" diameter of A119
  measures "d140" diameter of A120
  measures "d141" diameter of A121
  measures "d142" diameter of A122
  measures "d143" diameter of A123
  measures "d144" diameter of A124
  measures "d145" diameter of A125
  measures "d146" diameter of A126
  measures "d147" diameter of A127
  measures "d148" diameter of A128
  measures "d149" diameter of A131
  measures "d150" diameter of A130
  measures "d151" diameter of A129
  measures "d152" diameter of A132
extrude "Extrude3" cut sketch "Blinking Light House-PTH-drl_map" against normal blind 7.62 contours A1 | A2 | A3 | A4 | A5 | A6 | A7 | A8 | A9 | A10 | A11 | A12 | A13 | A14 | A15 | A16 | A17 | A18 | A19 | A20 | A21 | A22 | A23 | A24 | A25 | A26 | A27 | A28 | A29 | A30 | A31 | A32 | A33 | A34 | A35 | A36 | A37 | A38 | A39 | A40 | A41 | A42 | A43 | A44 | A45 | A46 | A47 | A48 | A49 | A50 | A51 | A52 | A54 | A55 | A56 | A57 | A58 | A59 | A60 | A61 | A62 | A63 | A64 | A65 | A66 | A67 | A68 | A69 | A70 | A71 | A72 | A73 | A74 | A75 | A76 | A77 | A78 | A79 | A80 | A81 | A82 | A83 | A84 | A85 | A86 | A87 | A88 | A89 | A90 | A91 | A92 | A93 | A94 | A95 | A96 | A97 | A98 | A99 | A100 | A101 | A102 | A103 | A104 | A105 | A106 | A107 | A108 | A109 | A110 | A111 | A112 | A113 | A114 | A115 | A116 | A117 | A118 | A119 | A120 | A121 | A122 | A123 | A124 | A125 | A126 | A127 | A128 | A129 | A130 | A131 | A132